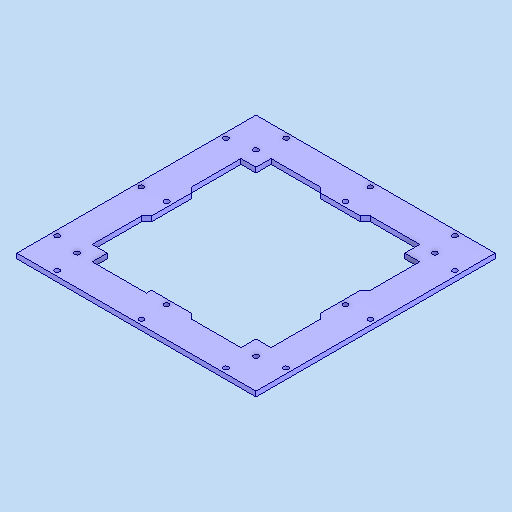
# Autodesk Inventor part: Carcasa_Interna
Saved by Autodesk Inventor 2027 (Build 310192000, 192)
## iProperties
Created: 2026-11-03
Part Number: Carcasa_Interna
Material: Plástico PAEK
Document SubType Name: Modeling
Designer: alex
Density: 1.32 g/cm^3
Appearance: Suave - Blanco
Author: alex
Autodesk Inventor part; units mm, degrees
ref_plane "YZ Plane" through (0, 0, 0) normal (1, 0, 0) x (0, 1, 0)
ref_plane "XZ Plane" through (0, 0, 0) normal (0, 1, 0) x (-1, 0, 0)
ref_plane "XY Plane" through (0, 0, 0) normal (0, 0, 1) x (1, 0, 0)
sketch "Boceto1" plane through (0, 0, 0) normal (0, 1, 0) x (-1, 0, 0)
  circle A0 centre (193.8277, 84.25) radius 2.5
  circle A1 centre (193.8277, 0.25) radius 2.5
  circle A2 centre (193.8277, -83.75) radius 2.5
  circle A3 centre (163.8277, -113.75) radius 2.5
  circle A4 centre (79.8277, -113.75) radius 2.5
  circle A5 centre (-4.1723, -113.75) radius 2.5
  circle A6 centre (-34.1723, -83.75) radius 2.5
  circle A7 centre (-34.1723, 0.25) radius 2.5
  circle A8 centre (-34.1723, 84.25) radius 2.5
  circle A9 centre (-4.1723, 114.25) radius 2.5
  circle A10 centre (79.8277, 114.25) radius 2.5
  circle A11 centre (163.8277, 114.25) radius 2.5
  line L0 (188.8277, 109.25) -> (-29.1723, 109.25)
  line L1 (-29.1723, 109.25) -> (-29.1723, -108.75)
  line L2 (-29.1723, -108.75) -> (188.8277, -108.75)
  line L3 (188.8277, -108.75) -> (188.8277, 109.25)
  line L4 (-24.1723, 104.25) -> (183.8277, 104.25)
  line L5 (183.8277, 104.25) -> (183.8277, -103.75)
  line L6 (183.8277, -103.75) -> (-24.1723, -103.75)
  line L7 (-24.1723, -103.75) -> (-24.1723, 104.25)
  line L8 (198.8277, 119.25) -> (-39.1723, 119.25)
  line L9 (-39.1723, 119.25) -> (-39.1723, -118.75)
  line L10 (-39.1723, -118.75) -> (198.8277, -118.75)
  line L11 (198.8277, -118.75) -> (198.8277, 119.25)
  line L12 (183.8277, 104.25) -> (153.8277, 104.25)
  line L13 (183.8277, 104.25) -> (183.8277, 74.25)
  line L14 (183.8277, 74.25) -> (153.8277, 104.25)
  line L15 (183.8277, -103.75) -> (183.8277, -73.75)
  line L16 (183.8277, -103.75) -> (153.8277, -103.75)
  line L17 (153.8277, -103.75) -> (183.8277, -73.75)
  line L18 (-24.1723, 104.25) -> (5.8277, 104.25)
  line L19 (-24.1723, 104.25) -> (-24.1723, 74.25)
  line L20 (-24.1723, 74.25) -> (5.8277, 104.25)
  line L21 (-24.1723, -103.75) -> (-24.1723, -73.75)
  line L22 (-24.1723, -103.75) -> (5.8277, -103.75)
  line L23 (5.8277, -103.75) -> (-24.1723, -73.75)
  point P0 (0, 0)
  point P1 (-233.5184, 131.3027)
  point P2 (-4.1723, -113.75)
  dimension "d24" = 5
  dimension "d25" = 5
  dimension "d26" = 5
  dimension "d30" = 5
  dimension "d31" = 5
  dimension "d32" = 5
  dimension "d33" = 5
  dimension "d34" = 5
  dimension "d35" = 5
  dimension "d48" = 5
  dimension "d49" = 5
  dimension "d50" = 5
  dimension "d51" = 208
  dimension "d52" = 208
  dimension "d53" = 10
  dimension "d55" = 10
  dimension "d56" = 5
  dimension "d57" = 10
  dimension "d58" = 5
  dimension "d59" = 5
  dimension "d60" = 5
  dimension "d61" = 5
  dimension "d62" = 5
  dimension "d63" = 5
  dimension "d64" = 5
  dimension "d65" = 5
  dimension "d66" = 5
  dimension "d67" = 5
  dimension "d68" = 5
  dimension "d69" = 10
  dimension "d70" = 5
  dimension "d71" = 30
  dimension "d72" = 30
  dimension "d73" = 30
  dimension "d74" = 30
  dimension "d75" = 30
  dimension "d76" = 30
  dimension "d77" = 30
  dimension "d78" = 30
  dimension "d81" = 84
  dimension "d82" = 84
  dimension "d83" = 84
  dimension "d84" = 84
  dimension "d85" = 84
  dimension "d86" = 84
  dimension "d87" = 35
  dimension "d88" = 84
  dimension "d89" = 84
  dimension "d90" = 35
  dimension "d91" = 35
  dimension "d92" = 35
  constraints: 48 end point, 12 centre point, 12 coincident, 8 point on line, 6 parallel, 3 horizontal, 3 perpendicular
  measures "d24" diameter of A0
  measures "d25" diameter of A1
  measures "d26" diameter of A2
  measures "d30" diameter of A6
  measures "d31" diameter of A7
  measures "d32" diameter of A8
  measures "d33" diameter of A9
  measures "d34" diameter of A10
  measures "d35" diameter of A11
  measures "d48" distance between parallel lines of L7 L1
  measures "d49" distance between parallel lines of L4 L0
  measures "d50" distance between parallel lines of L5 L3
  measures "d51" distance between parallel lines of L6 L4
  measures "d52" distance of L5.end L6.end
  measures "d53" distance between parallel lines of L8 L0
  measures "d55" distance between parallel lines of L3 L11
  measures "d56" distance between parallel lines of L6 L2
  measures "d57" distance between parallel lines of L10 L2
  measures "d58" distance from line of L3 A0.centre
  measures "d59" distance from line of L3 A1.centre
  measures "d60" distance from line of L3 A2.centre
  measures "d61" distance from line of L2 A3.centre
  measures "d62" distance from line of L2 A4.centre
  measures "d63" distance from line of L2 A5.centre
  measures "d64" distance from line of L1 A6.centre
  measures "d65" distance from line of L1 A7.centre
  measures "d66" distance from line of L1 point (-34.172, 84.25)
  measures "d67" distance from line of L0 A9.centre
  measures "d68" distance from line of L0 point (79.828, 114.25)
  measures "d69" distance between parallel lines of L9 L1
  measures "d70" distance from line of L0 A11.centre
  measures "d71" distance of L4.end L12.end
  measures "d72" distance of L4.end L13.end
  measures "d73" distance of L5.end L15.end
  measures "d74" distance of L5.end L16.end
  measures "d75" distance of L4.start L18.end
  measures "d76" distance of L4.start L19.end
  measures "d77" distance of L6.end L21.end
  measures "d78" distance of L6.end L22.end
  measures "d81" distance of A6.centre A7.centre
  measures "d82" distance of A8.centre A7.centre
  measures "d83" distance of A5.centre A4.centre
  measures "d84" distance of A3.centre A4.centre
  measures "d85" distance of A9.centre A10.centre
  measures "d86" distance of A11.centre A10.centre
  measures "d87" distance from line of L8 A0.centre
  measures "d88" distance of A1.centre A0.centre
  measures "d89" distance of A2.centre A1.centre
  measures "d90" distance from line of L10 A6.centre
  measures "d91" distance from line of point (-4.172, 114.25) L9
  measures "d92" distance from line of L9 A5.centre
extrude "Extrusión1" add sketch "Boceto1" along normal blind 5 contours L3 L2 L1 L0 | L4 L20 L7 | L4 L5 L14 | L23 L6 L7 | L5 L6 L17 | L11 L10 L9 L8
sketch "Boceto2" plane through (0, 5, 0) normal (0, 1, 0) x (1, 0, 0)
  line L0 (-153.8277, 103.75) -> (-5.8277, 103.75) projected
  line L1 (-79.8277, 103.75) -> (-79.8277, 83.75)
  line L2 (-5.8277, -104.25) -> (-153.8277, -104.25) projected
  line L3 (-79.8277, -104.25) -> (-79.8277, -84.25)
  line L4 (24.1723, 73.75) -> (24.1723, -74.25) projected
  line L5 (24.1723, -0.25) -> (4.1723, -0.25)
  line L6 (-183.8277, -74.25) -> (-183.8277, 73.75) projected
  line L7 (-183.8277, -0.25) -> (-163.8277, -0.25)
  line L8 (-183.8277, -0.25) -> (-183.8277, -20.25)
  line L9 (-183.8277, -0.25) -> (-183.8277, 19.75)
  line L10 (-183.8277, 19.75) -> (-163.8277, 19.75)
  line L11 (-163.8277, 19.75) -> (-183.8277, 19.75)
  line L12 (-183.8277, 19.75) -> (-183.8277, -20.25)
  line L13 (-183.8277, -20.25) -> (-163.8277, -20.25)
  line L14 (-163.8277, -20.25) -> (-163.8277, 19.75)
  line L15 (-99.8277, 83.75) -> (-59.8277, 83.75)
  line L16 (-59.8277, 83.75) -> (-59.8277, 103.75)
  line L17 (-59.8277, 103.75) -> (-99.8277, 103.75)
  line L18 (-99.8277, 103.75) -> (-99.8277, 83.75)
  line L19 (-153.8277, 103.75) -> (-5.8277, 103.75) projected
  line L20 (24.1723, 19.75) -> (4.1723, 19.75)
  line L21 (4.1723, 19.75) -> (4.1723, -20.25)
  line L22 (4.1723, -20.25) -> (24.1723, -20.25)
  line L23 (24.1723, -20.25) -> (24.1723, 19.75)
  line L24 (-59.8277, -84.25) -> (-99.8277, -84.25)
  line L25 (-99.8277, -84.25) -> (-99.8277, -104.25)
  line L26 (-99.8277, -104.25) -> (-59.8277, -104.25)
  line L27 (-59.8277, -104.25) -> (-59.8277, -84.25)
  line L28 (-59.8277, 83.75) -> (-39.8277, 103.75)
  line L29 (-59.8277, 83.75) -> (-31.5434, 83.75) construction
  line L30 (-99.8277, 83.75) -> (-119.8277, 103.75)
  line L31 (-163.8277, 19.75) -> (-183.8277, 39.75)
  line L32 (-163.8277, -20.25) -> (-183.8277, -40.25)
  line L33 (-99.8277, -84.25) -> (-119.8277, -104.25)
  line L34 (-59.8277, -84.25) -> (-39.8277, -104.25)
  line L35 (4.1723, -20.25) -> (24.1723, -40.25)
  line L36 (4.1723, 19.75) -> (24.1723, 39.75)
  circle A0 centre (-79.8277, 88.75) radius 2.5
  circle A1 centre (9.1723, -0.25) radius 2.5
  circle A2 centre (-79.8277, -89.25) radius 2.5
  circle A3 centre (-168.8277, -0.25) radius 2.5
  line L37 (-79.8277, 88.75) -> (9.1723, 88.75)
  line L38 (9.1723, 88.75) -> (9.1723, -0.25)
  line L39 (9.1723, -0.25) -> (-79.8277, -0.25)
  line L40 (-79.8277, -0.25) -> (-79.8277, 88.75)
  line L41 (-153.8277, -104.25) -> (-183.8277, -74.25) projected
  line L42 (9.1723, 88.75) -> (-168.8277, 88.75)
  line L43 (-168.8277, 88.75) -> (-168.8277, -89.25)
  line L44 (-168.8277, -89.25) -> (9.1723, -89.25)
  line L45 (9.1723, -89.25) -> (9.1723, 88.75)
  line L46 (-5.8277, 103.75) -> (24.1723, 103.75)
  line L47 (24.1723, 103.75) -> (24.1723, 73.75)
  line L48 (24.1723, 73.75) -> (-5.8277, 73.75)
  line L49 (-5.8277, 73.75) -> (-5.8277, 103.75)
  circle A4 centre (9.1723, 88.75) radius 2.5
  line L50 (24.1723, -74.25) -> (-5.8277, -104.25) projected
  line L51 (24.1723, -74.25) -> (-5.8277, -74.25)
  line L52 (-5.8277, -74.25) -> (-5.8277, -104.25)
  line L53 (-5.8277, -104.25) -> (24.1723, -104.25)
  line L54 (24.1723, -104.25) -> (24.1723, -74.25)
  circle A5 centre (9.1723, -89.25) radius 2.5
  line L55 (-183.8277, 73.75) -> (-153.8277, 103.75) projected
  line L56 (-153.8277, 103.75) -> (-183.8277, 103.75)
  line L57 (-183.8277, 103.75) -> (-183.8277, 73.75)
  line L58 (-183.8277, 73.75) -> (-153.8277, 73.75)
  line L59 (-153.8277, 73.75) -> (-153.8277, 103.75)
  line L60 (-183.8277, -74.25) -> (-153.8277, -74.25)
  line L61 (-153.8277, -74.25) -> (-153.8277, -104.25)
  line L62 (-153.8277, -104.25) -> (-183.8277, -104.25)
  line L63 (-183.8277, -104.25) -> (-183.8277, -74.25)
  circle A6 centre (-168.8277, 88.75) radius 2.5
  circle A7 centre (-168.8277, -89.25) radius 2.5
  point P0 (0, 0)
  point P1 (-59.8277, -94.25)
  point P2 (-167.0599, 90.5178)
  point P3 (-170.5954, 86.9823)
  point P4 (-170.5954, -87.4822)
  point P5 (-167.0599, -91.0177)
  point P6 (-99.8277, -89.25)
  point P7 (-153.8277, -89.25)
  point P8 (-168.8277, -74.25)
  point P9 (-168.8277, -25.25)
  point P10 (-168.8277, 24.75)
  point P11 (-168.8277, 73.75)
  point P12 (-153.8277, 88.75)
  point P13 (-104.8277, 88.75)
  point P14 (-54.8277, 88.75)
  point P15 (-5.8277, 88.75)
  point P16 (9.1723, 73.75)
  point P17 (9.1723, 24.75)
  point P18 (9.1723, -25.25)
  point P19 (9.1723, -74.25)
  point P20 (-5.8277, -89.25)
  point P21 (-54.8277, -89.25)
  dimension "d93" = 20
  dimension "d94" = 20
  dimension "d95" = 20
  dimension "d96" = 20
  dimension "d97" = 20
  dimension "d98" = 20
  dimension "d99" = 20
  dimension "d100" = 40
  dimension "d101" = 20
  dimension "d102" = 20
  dimension "d103" = 20
  dimension "d104" = 40
  dimension "d105" = 20
  dimension "d106" = 40
  dimension "d107" = 20
  dimension "d108" = 20
  dimension "d109" = 45
  dimension "d110" = 5
  dimension "d111" = 5
  dimension "d112" = 5
  dimension "d113" = 5
  dimension "d114" = 5
  dimension "d115" = 5
  dimension "d116" = 5
  dimension "d117" = 5
  dimension "d118" = 5
  dimension "d119" = 5
  dimension "d120" = 5
  dimension "d121" = 5
  constraints: 112 end point, 22 parallel, 22 point on line, 12 horizontal, 12 perpendicular, 8 centre point, 6 midpoint, 4 coincident, 2 vertical, 1 equal length
  measures "d93" distance of L1.start L1.end
  measures "d94" distance of L3.start L3.end
  measures "d95" distance of L5.start L5.end
  measures "d96" distance of L7.start L7.end
  measures "d97" distance of L7.start L8.end
  measures "d98" distance of L7.start L9.end
  measures "d99" distance of L9.end L10.end
  measures "d100" distance of L17.end L16.end
  measures "d101" distance of L16.end L15.end
  measures "d102" distance between parallel lines of L18 L1
  measures "d103" distance of L22.end L21.end
  measures "d104" distance of L21.end L20.end
  measures "d105" distance between parallel lines of L20 L5
  measures "d106" distance of L26.end L25.end
  measures "d107" distance of L25.end L24.end
  measures "d108" distance from line of point (-59.828, -94.25) L3
  measures "d109" angle of L29 L28
  measures "d110" diameter of A0
  measures "d111" distance from line of L15 L37.start
  measures "d112" diameter of A1
  measures "d113" distance from line of L21 L38.end
  measures "d114" diameter of A2
  measures "d115" distance from line of L24 A2.centre
  measures "d116" diameter of A3
  measures "d117" distance from line of A3.centre L14
  measures "d118" diameter of A4
  measures "d119" diameter of A5
  measures "d120" diameter of A6
  measures "d121" diameter of A7
extrude "Extrusión2" add sketch "Boceto2" against normal blind 5 contours L59 L42 A6 L55 | L0 L30 L42 L59 | L0 L18 L42 L30 | L59 L58 L43 A6 L42 | L0 L1 A0 L42 L18 | L42 L18 L30 | A6 L43 L58 L55 | L58 L43 L31 L6 | L0 L16 L37 A0 L1 | L42 A0 L1 L15 L18 | L31 L43 L10 L6 | L0 L28 L37 L16 | L1 A0 L37 L16 L15 | L10 L43 A3 L7 L6 | L31 L10 L43 | L0 L49 L37 L28 | L37 L28 L16 | L7 A3 L43 L13 L6 | L10 L14 L7 A3 L43 | L46 L47 L48 L38 A4 L37 L49 | L21 L20 L38 A1 L5 | L5 A1 L45 L22 L21 | L13 L43 L32 L6 | L14 L13 L43 A3 L7 | L37 A4 L38 L48 L49 | L36 L38 L20 | L22 L45 L35 | L32 L43 L60 L6 | L13 L32 L43 | L4 L36 L38 L48 | L38 L20 L4 L5 A1 | A1 L5 L4 L22 L45 | L38 L36 L4 L20 | L22 L4 L35 L45 | L35 L4 L51 L45 | L60 L43 A7 L41 | L51 L50 A5 L45 | L45 A5 L44 L52 L51 | L60 L61 L44 A7 L43 | L54 L53 L50 A5 | A7 L44 L61 L41 | L61 L44 L33 L2 | A5 L50 L52 L44 | L52 L2 L34 L44 | L33 L44 L25 L2 | L44 L27 L34 | L34 L2 L27 L44 | L25 L44 A2 L3 L2 | L27 L44 A2 L3 L24 | L27 L2 L3 A2 L44 | L24 L3 A2 L44 L25
hole "Agujero1" at (9.1723, 5, -88.75) at (9.1723, 5, 89.25) at (-168.8277, 5, 89.25) at (-168.8277, 5, -88.75) direction (0, -1, 0) diameter 5 end through all
